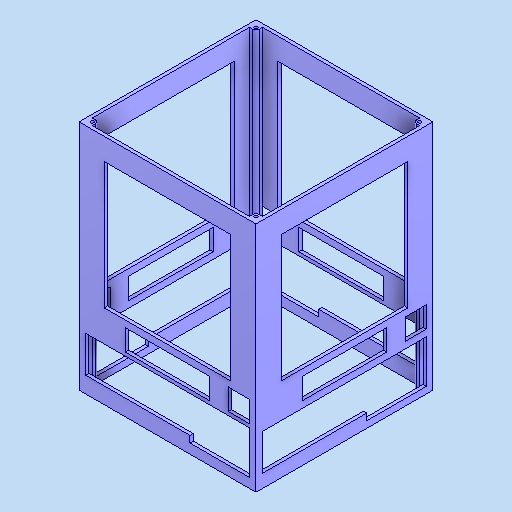
# Autodesk Inventor part: Carcasa_Externa
Saved by Autodesk Inventor 2027 (Build 310192000, 192)
## iProperties
Created: 2026-11-02
Part Number: Carcasa_Externa
Material: Plástico PAEK
Document SubType Name: Modeling
Designer: alex
Density: 1.32 g/cm^3
Appearance: Suave - Blanco
Author: alex
Autodesk Inventor part; units mm, degrees
ref_plane "YZ Plane" through (0, 0, 0) normal (1, 0, 0) x (0, 1, 0)
sketch "Boceto1" plane through (0, 0, 0) normal (0, 0, 1) x (1, 0, 0)
  line L0 (460, 450) -> (192, 450)
  line L1 (192, 450) -> (192, 98)
  line L2 (192, 98) -> (460, 98)
  line L3 (460, 98) -> (460, 450)
  line L4 (422, 225) -> (230, 225)
  line L5 (230, 225) -> (230, 417)
  line L6 (230, 417) -> (422, 417)
  line L7 (422, 417) -> (422, 225)
  line L8 (450, 183) -> (418, 183)
  line L9 (418, 183) -> (418, 215)
  line L10 (418, 215) -> (450, 215)
  line L11 (450, 215) -> (450, 183)
  line L12 (390, 183) -> (262, 183)
  line L13 (262, 183) -> (262, 215)
  line L14 (262, 215) -> (390, 215)
  line L15 (390, 215) -> (390, 183)
  line L16 (202, 122.6114) -> (202, 177.6114)
  line L17 (202, 177.6114) -> (450, 177.6114)
  line L18 (450, 177.6114) -> (450, 122.6114)
  line L19 (360, 122.6114) -> (360, 112.6114)
  line L20 (360, 112.6114) -> (450, 112.6114)
  line L21 (450, 112.6114) -> (450, 122.6114)
  line L22 (450, 177.6114) -> (450, 112.6114)
  line L23 (360, 112.6114) -> (360, 122.6114)
  line L24 (360, 122.6114) -> (202, 122.6114)
  point P0 (0, 0)
  point P1 (390, 199)
  dimension "d0" = 268
  dimension "d1" = 352
  dimension "d2" = 192
  dimension "d3" = 192
  dimension "d4" = 33
  dimension "d5" = 38
  dimension "d6" = 32
  dimension "d7" = 32
  dimension "d8" = 10
  dimension "d9" = 10
  dimension "d10" = 128
  dimension "d11" = 32
  dimension "d12" = 10
  dimension "d13" = 28
  dimension "d14" = 248
  dimension "d15" = 55
  dimension "d16" = 10
  dimension "d17" = 90
  dimension "d18" = 10
  constraints: 50 end point, 11 parallel, 4 perpendicular, 1 collinear, 1 midpoint
  measures "d0" distance of L2.end L1.end
  measures "d1" distance of L1.end L0.end
  measures "d2" distance of L5.end L6.end
  measures "d3" distance of L4.end L5.end
  measures "d4" distance between parallel lines of L6 L0
  measures "d5" distance between parallel lines of L3 L7
  measures "d6" distance of L9.end L10.end
  measures "d7" distance of L8.end L9.end
  measures "d8" distance between parallel lines of L3 L11
  measures "d9" distance between parallel lines of L10 L4
  measures "d10" distance of L13.end L14.end
  measures "d11" distance of L12.end L13.end
  measures "d12" distance between parallel lines of L4 L14
  measures "d13" distance from line of L9 point (390, 199)
  measures "d14" distance of L16.end L17.end
  measures "d15" distance of L16.start L16.end
  measures "d16" distance between parallel lines of L3 L18
  measures "d17" distance of L20.end L19.end
  measures "d18" distance of L19.end L19.start
extrude "Extrusión1" add sketch "Boceto1" along normal blind 5
ref_plane "Plano de trabajo1" through (0, 0, -263) normal (0, 0, 1) x (1, 0, 0)
sketch "Boceto2" plane through (0, 0, -263) normal (0, 0, 1) x (1, 0, 0)
  line L0 (192, 450) -> (192, 98) projected
  line L1 (192, 98) -> (460, 98) projected
  line L2 (192, 450) -> (460, 450)
  line L3 (460, 450) -> (460, 98)
  line L4 (460, 98) -> (192, 98)
  line L5 (192, 98) -> (192, 450)
  line L6 (230, 225) -> (230, 417) projected
  line L7 (422, 225) -> (230, 225) projected
  line L8 (230, 417) -> (422, 417)
  line L9 (422, 417) -> (422, 225)
  line L10 (422, 225) -> (230, 225)
  line L11 (230, 225) -> (230, 417)
  line L12 (202, 177.6114) -> (450, 177.6114) projected
  line L13 (202, 177.6114) -> (202, 112.6114)
  line L14 (202, 112.6114) -> (292, 112.6114)
  line L15 (292, 112.6114) -> (292, 122.6114)
  line L16 (360, 122.6114) -> (202, 122.6114) projected
  line L17 (292, 122.6114) -> (450, 122.6114)
  line L18 (450, 177.6114) -> (450, 112.6114) projected
  line L19 (450, 122.6114) -> (450, 177.6114)
  line L20 (450, 177.6114) -> (202, 177.6114)
  line L21 (202, 215) -> (234, 215)
  line L22 (234, 215) -> (234, 183)
  line L23 (234, 183) -> (202, 183)
  line L24 (202, 183) -> (202, 215)
  line L25 (262, 183) -> (262, 215) projected
  line L26 (262, 215) -> (390, 215)
  line L27 (390, 215) -> (390, 183)
  line L28 (390, 183) -> (262, 183)
  line L29 (262, 183) -> (262, 215)
  point P0 (0, 0)
  dimension "d22" = 90
  dimension "d23" = 32
  dimension "d24" = 32
  dimension "d25" = 10
  dimension "d26" = 10
  constraints: 44 end point, 9 parallel, 8 perpendicular, 4 horizontal, 2 point on line, 1 collinear
  measures "d22" distance of L13.end L14.end
  measures "d23" distance of L22.end L23.end
  measures "d24" distance of L21.end L22.end
  measures "d25" distance between parallel lines of L21 L7
  measures "d26" distance between parallel lines of L0 L24
extrude "Extrusión2" add sketch "Boceto2" along normal blind 5
sketch "Boceto3" plane through (460, 98, 0) normal (1, 0, 0) x (0, 0, -1)
  line L0 (-5, 352) -> (-5, 0) projected
  line L1 (263, 352) -> (263, 0) projected
  line L2 (-5, 352) -> (263, 352)
  line L3 (263, 352) -> (263, 0)
  line L4 (263, 0) -> (-5, 0)
  line L5 (-5, 0) -> (-5, 352)
  line L6 (33, 319) -> (225, 319)
  line L7 (225, 319) -> (225, 127)
  line L8 (225, 127) -> (33, 127)
  line L9 (33, 127) -> (33, 319)
  line L10 (65, 117) -> (193, 117)
  line L11 (193, 117) -> (193, 85)
  line L12 (193, 85) -> (65, 85)
  line L13 (65, 85) -> (65, 117)
  line L14 (221, 117) -> (253, 117)
  line L15 (253, 117) -> (253, 85)
  line L16 (253, 85) -> (221, 85)
  line L17 (221, 85) -> (221, 117)
  line L18 (5, 75) -> (253, 75)
  line L19 (253, 75) -> (253, 20)
  line L20 (253, 20) -> (5, 20)
  line L21 (5, 20) -> (5, 75)
  line L22 (253, 20) -> (163, 20)
  line L23 (163, 20) -> (163, 10)
  line L24 (163, 10) -> (253, 10)
  line L25 (253, 10) -> (253, 20)
  point P0 (0, -98)
  point P1 (129, 352)
  point P2 (263, 352)
  point P3 (-5, 0)
  point P4 (163, 20)
  dimension "d29" = 192
  dimension "d30" = 192
  dimension "d31" = 33
  dimension "d32" = 38
  dimension "d33" = 128
  dimension "d34" = 32
  dimension "d35" = 70
  dimension "d36" = 10
  dimension "d37" = 32
  dimension "d38" = 32
  dimension "d39" = 10
  dimension "d40" = 10
  dimension "d41" = 248
  dimension "d42" = 55
  dimension "d43" = 10
  dimension "d44" = 10
  dimension "d45" = 90
  dimension "d46" = 10
  constraints: 48 end point, 12 parallel, 6 horizontal, 6 perpendicular, 1 midpoint
  measures "d29" distance of L7.end L8.end
  measures "d30" distance of L6.end L7.end
  measures "d31" distance from line of L6 point (129, 352)
  measures "d32" distance between parallel lines of L9 L0
  measures "d33" distance of L11.end L12.end
  measures "d34" distance of L10.end L11.end
  measures "d35" distance between parallel lines of L0 L13
  measures "d36" distance between parallel lines of L8 L10
  measures "d37" distance of L15.end L16.end
  measures "d38" distance of L14.end L15.end
  measures "d39" distance between parallel lines of L8 L14
  measures "d40" distance between parallel lines of L15 L1
  measures "d41" distance of L19.end L20.end
  measures "d42" distance of L18.end L19.end
  measures "d43" distance between parallel lines of L0 L21
  measures "d44" distance between parallel lines of L18 L12
  measures "d45" distance of L24.end L23.end
  measures "d46" distance of L23.end L22.end
extrude "Extrusión3" add sketch "Boceto3" against normal blind 5
ref_plane "Plano de trabajo2" through (192, 98, 5) normal (1, 0, 0) x (0, 0, -1)
sketch "Boceto4" plane through (192, 98, 5) normal (1, 0, 0) x (0, 0, -1)
  line L0 (268, 0) -> (263, 0) projected
  line L1 (0, 352) -> (268, 352)
  line L2 (268, 352) -> (268, 0)
  line L3 (268, 0) -> (0, 0)
  line L4 (0, 0) -> (0, 352)
  line L5 (230, 319) -> (38, 319) projected
  line L6 (230, 127) -> (230, 319) projected
  line L7 (38, 319) -> (230, 319)
  line L8 (230, 319) -> (230, 127)
  line L9 (230, 127) -> (38, 127)
  line L10 (38, 127) -> (38, 319)
  line L11 (198, 85) -> (70, 85) projected
  line L12 (70, 117) -> (198, 117)
  line L13 (198, 117) -> (198, 85)
  line L14 (198, 85) -> (70, 85)
  line L15 (70, 85) -> (70, 117)
  line L16 (10, 75) -> (10, 20) projected
  line L17 (258, 10) -> (258, 75) projected
  line L18 (10, 75) -> (258, 75)
  line L19 (258, 75) -> (258, 20)
  line L20 (258, 20) -> (10, 20)
  line L21 (10, 20) -> (10, 75)
  line L22 (168, 20) -> (10, 20) projected
  line L23 (10, 20) -> (100, 20)
  line L24 (100, 20) -> (100, 10)
  line L25 (100, 10) -> (10, 10)
  line L26 (10, 10) -> (10, 20)
  line L27 (10, 117) -> (42, 117)
  line L28 (42, 117) -> (42, 85)
  line L29 (42, 85) -> (10, 85)
  line L30 (10, 85) -> (10, 117)
  point P0 (5, -98)
  point P1 (10, 101)
  point P2 (258, 75)
  point P3 (70, 85)
  dimension "d50" = 55
  dimension "d51" = 90
  dimension "d52" = 10
  dimension "d53" = 32
  dimension "d54" = 32
  dimension "d55" = 10
  dimension "d56" = 10
  constraints: 48 end point, 12 parallel, 6 horizontal, 6 perpendicular, 1 midpoint, 1 point on line
  measures "d50" distance of L18.end L19.end
  measures "d51" distance of L24.end L25.end
  measures "d52" distance of L23.end L24.end
  measures "d53" distance of L28.end L29.end
  measures "d54" distance of L27.end L28.end
  measures "d55" distance between parallel lines of L27 L9
  measures "d56" distance from line of point (10, 101) L4
extrude "Extrusión4" add sketch "Boceto4" along normal blind 5
sketch "Boceto5" plane through (192, 450, 5) normal (0, 1, 0) x (1, 0, 0)
  circle A0 centre (10, 10) radius 2.5
  circle A1 centre (10, 258) radius 2.5
  circle A2 centre (258, 10) radius 2.5
  circle A3 centre (258, 258) radius 2.5
  line L0 (263, 263) -> (5, 263) projected
  line L1 (263, 5) -> (263, 263) projected
  line L2 (263, 5) -> (5, 5) projected
  line L3 (5, 263) -> (5, 5) projected
  line L4 (0, 10) -> (5, 10) projected
  circle A4 centre (10, 10) radius 5
  line L5 (5, 5) -> (263, 5) projected
  line L6 (10, 5) -> (5, 5)
  line L7 (5, 5) -> (5, 10)
  circle A5 centre (10, 258) radius 5
  line L8 (10, 268) -> (10, 263) projected
  line L9 (10, 263) -> (5, 263)
  circle A6 centre (258, 10) radius 5
  line L10 (258, 5) -> (263, 5)
  line L11 (268, 10) -> (263, 10) projected
  line L12 (263, 10) -> (263, 5)
  circle A7 centre (258, 258) radius 5
  line L13 (15, 10) -> (15, 5)
  line L14 (10, 15) -> (5, 15)
  line L15 (10, 253) -> (5, 253)
  line L16 (15, 258) -> (15, 263)
  line L17 (253, 10) -> (253, 5)
  line L18 (258, 15) -> (263, 15)
  line L19 (258, 253) -> (263, 253)
  line L20 (253, 258) -> (253, 263)
  point P0 (-192, 5)
  point P1 (253, 5)
  dimension "d59" = 5
  dimension "d60" = 5
  dimension "d61" = 5
  dimension "d62" = 5
  dimension "d63" = 5
  dimension "d64" = 5
  dimension "d65" = 5
  dimension "d66" = 5
  dimension "d67" = 5
  dimension "d68" = 5
  dimension "d69" = 5
  dimension "d70" = 5
  constraints: 26 end point, 18 point on line, 11 point on circle, 8 centre point, 8 tangent, 4 coincident, 4 collinear, 4 perpendicular
  measures "d59" diameter of A0
  measures "d60" diameter of A1
  measures "d61" diameter of A2
  measures "d62" diameter of A3
  measures "d63" distance from line of L0 A3.centre
  measures "d64" distance from line of L1 A3.centre
  measures "d65" distance from line of L1 A2.centre
  measures "d66" distance from line of L2 A2.centre
  measures "d67" distance from line of L2 A0.centre
  measures "d68" distance from line of L3 A0.centre
  measures "d69" distance from line of L3 A1.centre
  measures "d70" distance from line of L0 A1.centre
extrude "Extrusión5" add sketch "Boceto5" against normal blind 352 contours L0 A7 L20 | L16 A5 L0 | L0 L1 A7 | A7 | A5 L3 L0 | A5 | L1 L19 A7 | A5 L15 L3 | L1 A6 L18 | L14 A4 L3 | A6 | L1 L2 A6 | A4 L2 L3 | A4 | L2 L17 A6 | A4 L13 L2
sketch "Boceto6" plane through (192, 98, 5) normal (0, -1, 0) x (1, 0, 0)
  arc A0 (10, -15) -> (15, -10) centre (10, -10) ccw projected
  circle A1 centre (10, -10) radius 2.5
  line L0 (5, -15) -> (10, -15) projected
  arc A2 (10, -15) -> (15, -10) centre (10, -10) ccw
  line L1 (15, -5) -> (15, -10) projected
  line L2 (15, -10) -> (15, -5)
  line L3 (15, -5) -> (253, -5)
  line L4 (253, -5) -> (253, -10)
  arc A3 (253, -10) -> (258, -15) centre (258, -10) ccw projected
  line L5 (263, -15) -> (263, -168) projected
  line L6 (258, -15) -> (263, -15)
  line L7 (263, -258) -> (263, -253) projected
  line L8 (263, -15) -> (263, -253)
  line L9 (263, -253) -> (258, -253)
  arc A4 (258, -253) -> (253, -258) centre (258, -258) ccw projected
  line L10 (15, -263) -> (253, -263) projected
  line L11 (253, -258) -> (253, -263)
  line L12 (15, -263) -> (15, -258) projected
  line L13 (253, -263) -> (15, -263)
  line L14 (15, -263) -> (15, -258)
  line L15 (5, -253) -> (5, -15)
  arc A5 (258, -253) -> (253, -258) centre (258, -258) ccw
  arc A6 (15, -258) -> (10, -253) centre (10, -258) ccw projected
  arc A7 (15, -258) -> (10, -253) centre (10, -258) ccw
  line L16 (10, -253) -> (5, -253) projected
  line L17 (10, -253) -> (5, -253)
  point P0 (-192, -5)
  constraints: 22 end point, 7 perpendicular, 6 point on circle, 4 centre point, 2 concentric, 1 coincident, 1 collinear, 1 horizontal, 1 parallel, 1 point on line, 1 vertical
